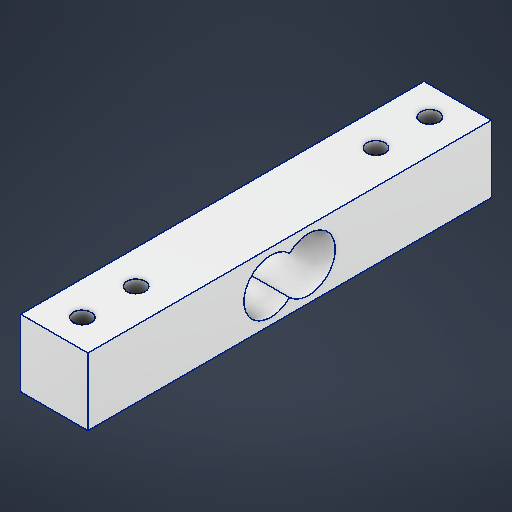
# Autodesk Inventor part: 로드셀 센서
Saved by Autodesk Inventor 2026.2 (Build 302298010, 298A)
## iProperties
Created: 2026-03-20
Part Number: 로드셀 센서
Material: 알루미늄 6061
Document SubType Name: Modeling
Designer: work
Density: 2.7 g/cm^3
Appearance: 알루미늄 - 평지
Author: work
Autodesk Inventor part; units mm, degrees
ref_plane "YZ Plane" through (0, 0, 0) normal (1, 0, 0) x (0, 1, 0)
ref_plane "XZ Plane" through (0, 0, 0) normal (0, 1, 0) x (-1, 0, 0)
sketch "스케치1" plane through (0, 0, 0) normal (0, 1, 0) x (-1, 0, 0)
  line L0 (0, 0) -> (12.5, 0)
  line L1 (12.5, 0) -> (12.5, -75)
  line L2 (12.5, -75) -> (0, -75)
  line L3 (0, -75) -> (0, 0)
  dimension "d0" = 12.5
  dimension "d1" = 75
  constraints: 8 end point, 2 parallel, 1 horizontal, 1 perpendicular
  measures "d0" distance of L1.end L2.end
  measures "d1" distance of L0.end L1.end
extrude "돌출1" add sketch "스케치1" along normal blind 12.5
sketch "스케치2" plane through (0, 0, 0) normal (1, 0, 0) x (0, 0, -1)
  line L0 (75, 12.5) -> (0, 12.5) projected
  line L1 (37.5, 12.5) -> (37.5, 0) construction
  line L2 (75, 0) -> (0, 0) projected
  line L3 (34, 6.25) -> (41, 6.25) construction
  circle A0 centre (41, 6.25) radius 5
  circle A1 centre (34, 6.25) radius 5
  point P0 (37.5, 6.25)
  point P1 (37.5, 2.6793)
  point P2 (37.5, 9.8207)
  dimension "d4" = 10
  dimension "d5" = 10
  dimension "d6" = 17
  constraints: 4 end point, 4 midpoint, 2 centre point, 2 coincident, 1 horizontal
  measures "d4" diameter of A0
  measures "d5" diameter of A1
extrude "돌출2" cut sketch "스케치2" against normal blind 12.5
sketch "스케치3" plane through (0, 12.5, 0) normal (0, 1, 0) x (1, 0, 0)
  line L0 (-12.5, 0) -> (0, 0) projected
  line L1 (-6.25, 0) -> (-6.25, 75) construction
  line L2 (0, 75) -> (-12.5, 75) projected
  circle A0 centre (-6.25, 5.2) radius 1.7
  circle A1 centre (-6.25, 15.2) radius 1.7
  dimension "d9" = 3.4
  dimension "d10" = 3.4
  dimension "d11" = 5.2
  dimension "d12" = 6.6
  constraints: 3 midpoint, 2 centre point, 2 end point, 2 point on line
  measures "d9" diameter of A0
  measures "d10" diameter of A1
  measures "d11" distance of A0.centre point (-6.25, 0)
extrude "돌출3" cut sketch "스케치3" against normal through all
ref_plane "작업 평면1" through (-12.5, 0, -37.5) normal (0, 0, 1) x (1, 0, 0)
mirror "미러1" about plane through (-12.5, 0, -37.5) normal (0, 0, 1) of "돌출3"
